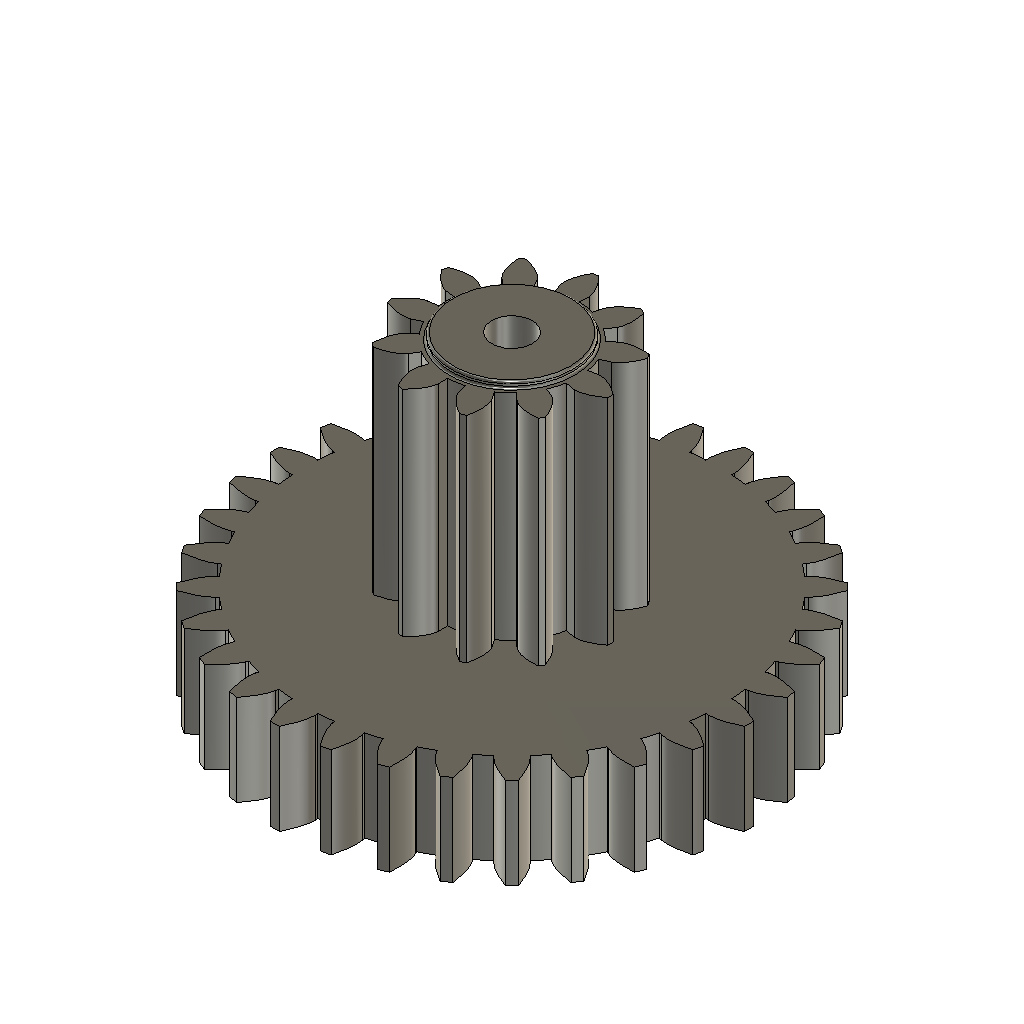
6R2907511A_32T-11T_Gear (Autodesk Fusion 360 design; units mm, degrees)
description: Spur Gear; Module: 0.69; Num Teeth: 32; Pressure Angle: 20.0; Backlash: 0.10 mm
part number: 2026-10-02-15-58-56-443
Autodesk Fusion 360 part; units mm, degrees
(part 1 of 7)
sketch "Base Circle" plane through (0, 0, 0) normal (0, 0, 1) x (1, 0, 0)
  circle A0 centre (0, 0) radius 10.24167
  circle A1 centre (0, 0) radius 1
extrude "Extrude1" add sketch "Base Circle" along normal blind 4.5 contours A0 picked at (7.122983, -0.508814) makes body 1
sketch "Gear Tooth" plane through (0, 0, 0) normal (0, 0, 1) x (1, 0, 0)
  spline S0 degree 5 poles (10.354449, -0.639965) (10.358374, -0.640208) (10.366227, -0.640603) (10.378011, -0.640924) (10.393732, -0.640838) (10.413398, -0.640021) (10.433079, -0.63869) (10.452771, -0.637035) (10.472474, -0.635204) (10.492186, -0.633256) (10.511906, -0.631191) (10.531631, -0.628972) (10.55136, -0.626547) (10.571092, -0.62388) (10.590826, -0.620964) (10.610561, -0.617818) (10.630298, -0.614469) (10.650036, -0.610951) (10.669774, -0.607289) (10.689512, -0.603492) (10.709251, -0.59956) (10.728988, -0.595488) (10.748725, -0.591267) (10.768459, -0.586892) (10.788192, -0.582365) (10.807922, -0.577689) (10.827649, -0.572872) (10.847374, -0.567922) (10.867095, -0.562843) (10.886813, -0.557639) (10.906526, -0.552312) (10.926236, -0.546861) (10.945941, -0.541285) (10.965642, -0.535586) (10.985337, -0.529764) (11.005027, -0.523821) (11.024712, -0.517759) (11.044391, -0.511582) (11.064064, -0.50529) (11.08373, -0.498885) (11.10339, -0.492368) (11.123044, -0.485741) (11.14269, -0.479003) (11.162329, -0.472156) (11.181961, -0.465201) (11.201585, -0.458138) (11.221201, -0.450968) (11.240809, -0.443694) (11.260409, -0.436315) (11.28, -0.428833) (11.299582, -0.421248) (11.319155, -0.413562) (11.33872, -0.405774) (11.358274, -0.397886) (11.377819, -0.389899) (11.397354, -0.381812) (11.41688, -0.373627) (11.436394, -0.365345) (11.455899, -0.356966) (11.475393, -0.34849) (11.494875, -0.339919) (11.514347, -0.331253) (11.533808, -0.322492) (11.553257, -0.313638) (11.572695, -0.304689) (11.592121, -0.295649) (11.611534, -0.286515) (11.630936, -0.277291) (11.650324, -0.267975) (11.6697, -0.258568) (11.689064, -0.249071) (11.704544, -0.241401) (11.716149, -0.235607) (11.723883, -0.231727) (11.727749, -0.229783) knots 0 0 0 0 0 0 0.01428571 0.02857143 0.04285714 0.05714286 0.07142857 0.08571429 0.1 0.11428571 0.12857143 0.14285714 0.15714286 0.17142857 0.18571429 0.2 0.21428571 0.22857143 0.24285714 0.25714286 0.27142857 0.28571429 0.3 0.31428571 0.32857143 0.34285714 0.35714286 0.37142857 0.38571429 0.4 0.41428571 0.42857143 0.44285714 0.45714286 0.47142857 0.48571429 0.5 0.51428571 0.52857143 0.54285714 0.55714286 0.57142857 0.58571429 0.6 0.61428571 0.62857143 0.64285714 0.65714286 0.67142857 0.68571429 0.7 0.71428571 0.72857143 0.74285714 0.75714286 0.77142857 0.78571429 0.8 0.81428571 0.82857143 0.84285714 0.85714286 0.87142857 0.88571429 0.9 0.91428571 0.92857143 0.94285714 0.95714286 0.97142857 0.98571429 1 1 1 1 1 1
  spline S1 degree 5 poles (10.354449, 0.639965) (10.358374, 0.640208) (10.366227, 0.640603) (10.378011, 0.640924) (10.393732, 0.640838) (10.413398, 0.640021) (10.433079, 0.63869) (10.452771, 0.637035) (10.472474, 0.635204) (10.492186, 0.633256) (10.511906, 0.631191) (10.531631, 0.628972) (10.55136, 0.626547) (10.571092, 0.62388) (10.590826, 0.620964) (10.610561, 0.617818) (10.630298, 0.614469) (10.650036, 0.610951) (10.669774, 0.607289) (10.689512, 0.603492) (10.709251, 0.59956) (10.728988, 0.595488) (10.748725, 0.591267) (10.768459, 0.586892) (10.788192, 0.582365) (10.807922, 0.577689) (10.827649, 0.572872) (10.847374, 0.567922) (10.867095, 0.562843) (10.886813, 0.557639) (10.906526, 0.552312) (10.926236, 0.546861) (10.945941, 0.541285) (10.965642, 0.535586) (10.985337, 0.529764) (11.005027, 0.523821) (11.024712, 0.517759) (11.044391, 0.511582) (11.064064, 0.50529) (11.08373, 0.498885) (11.10339, 0.492368) (11.123044, 0.485741) (11.14269, 0.479003) (11.162329, 0.472156) (11.181961, 0.465201) (11.201585, 0.458138) (11.221201, 0.450968) (11.240809, 0.443694) (11.260409, 0.436315) (11.28, 0.428833) (11.299582, 0.421248) (11.319155, 0.413562) (11.33872, 0.405774) (11.358274, 0.397886) (11.377819, 0.389899) (11.397354, 0.381812) (11.41688, 0.373627) (11.436394, 0.365345) (11.455899, 0.356966) (11.475393, 0.34849) (11.494875, 0.339919) (11.514347, 0.331253) (11.533808, 0.322492) (11.553257, 0.313638) (11.572695, 0.304689) (11.592121, 0.295649) (11.611534, 0.286515) (11.630936, 0.277291) (11.650324, 0.267975) (11.6697, 0.258568) (11.689064, 0.249071) (11.704544, 0.241401) (11.716149, 0.235607) (11.723883, 0.231727) (11.727749, 0.229783) knots 0 0 0 0 0 0 0.01428571 0.02857143 0.04285714 0.05714286 0.07142857 0.08571429 0.1 0.11428571 0.12857143 0.14285714 0.15714286 0.17142857 0.18571429 0.2 0.21428571 0.22857143 0.24285714 0.25714286 0.27142857 0.28571429 0.3 0.31428571 0.32857143 0.34285714 0.35714286 0.37142857 0.38571429 0.4 0.41428571 0.42857143 0.44285714 0.45714286 0.47142857 0.48571429 0.5 0.51428571 0.52857143 0.54285714 0.55714286 0.57142857 0.58571429 0.6 0.61428571 0.62857143 0.64285714 0.65714286 0.67142857 0.68571429 0.7 0.71428571 0.72857143 0.74285714 0.75714286 0.77142857 0.78571429 0.8 0.81428571 0.82857143 0.84285714 0.85714286 0.87142857 0.88571429 0.9 0.91428571 0.92857143 0.94285714 0.95714286 0.97142857 0.98571429 1 1 1 1 1 1
  arc A0 (11.727749, -0.229783) -> (11.727749, 0.229783) centre (0, 0) ccw
  line L0 (10.212184, -0.631172) -> (10.354449, -0.639965)
  line L1 (10.212184, 0.631172) -> (10.354449, 0.639965)
  line L2 (10.212184, -0.631172) -> (10.212184, 0.631172)
  point P0 (10.45165, -0.637089)
  point P1 (10.549289, -0.626753)
  point P2 (10.647192, -0.61143)
  point P3 (10.745282, -0.591976)
  point P4 (10.843507, -0.56887)
  point P5 (10.941824, -0.542429)
  point P6 (11.040197, -0.512879)
  point P7 (11.138591, -0.48039)
  point P8 (11.236976, -0.445097)
  point P9 (11.335322, -0.407108)
  point P10 (11.4336, -0.366512)
  point P11 (11.531782, -0.323384)
  point P12 (11.62984, -0.27779)
  point P13 (10.45165, 0.637089)
  point P14 (10.549289, 0.626753)
  point P15 (10.647192, 0.61143)
  point P16 (10.745282, 0.591976)
  point P17 (10.843507, 0.56887)
  point P18 (10.941824, 0.542429)
  point P19 (11.040197, 0.512879)
  point P20 (11.138591, 0.48039)
  point P21 (11.236976, 0.445097)
  point P22 (11.335322, 0.407108)
  point P23 (11.4336, 0.366512)
  point P24 (11.531782, 0.323384)
  point P25 (11.62984, 0.27779)
extrude "Extrude2" add sketch "Gear Tooth" along normal blind 4.5 contours S0 S1 A0 L0 L1 L2 picked at (11.141488, 0.130034) bodies 1
fillet "Fillet1" radius 0.4 2 edges at (10.222164, -0.631789, 2.25) (10.222164, 0.631789, 2.25) on bodies 1
pattern_circular "C-Pattern1" count 32 over 360 about axis through (0, 0, 0) along (0, 0, 1) of "Extrude2", "Fillet1"
sketch "Diametrial Pitch Circle" plane through (0, 0, 0) normal (0, 0, 1) x (1, 0, 0)
  circle A0 centre (0, 0) radius 11.04 construction
sketch "Base Circle (1)" plane through (0, 0, 0) normal (0, 0, 1) x (1, 0, 0)
  circle A0 centre (0, 0) radius 10.24167
  circle A1 centre (0, 0) radius 1
extrude "Extrude3" add sketch "Base Circle (1)" along normal blind 4.5 separate body contours A0 picked at (7.122983, -0.508814) makes body 2
sketch "Gear Tooth (1)" plane through (0, 0, 0) normal (0, 0, 1) x (1, 0, 0)
  spline S0 degree 5 poles (10.354449, -0.639965) (10.358374, -0.640208) (10.366227, -0.640603) (10.378011, -0.640924) (10.393732, -0.640838) (10.413398, -0.640021) (10.433079, -0.63869) (10.452771, -0.637035) (10.472474, -0.635204) (10.492186, -0.633256) (10.511906, -0.631191) (10.531631, -0.628972) (10.55136, -0.626547) (10.571092, -0.62388) (10.590826, -0.620964) (10.610561, -0.617818) (10.630298, -0.614469) (10.650036, -0.610951) (10.669774, -0.607289) (10.689512, -0.603492) (10.709251, -0.59956) (10.728988, -0.595488) (10.748725, -0.591267) (10.768459, -0.586892) (10.788192, -0.582365) (10.807922, -0.577689) (10.827649, -0.572872) (10.847374, -0.567922) (10.867095, -0.562843) (10.886813, -0.557639) (10.906526, -0.552312) (10.926236, -0.546861) (10.945941, -0.541285) (10.965642, -0.535586) (10.985337, -0.529764) (11.005027, -0.523821) (11.024712, -0.517759) (11.044391, -0.511582) (11.064064, -0.50529) (11.08373, -0.498885) (11.10339, -0.492368) (11.123044, -0.485741) (11.14269, -0.479003) (11.162329, -0.472156) (11.181961, -0.465201) (11.201585, -0.458138) (11.221201, -0.450968) (11.240809, -0.443694) (11.260409, -0.436315) (11.28, -0.428833) (11.299582, -0.421248) (11.319155, -0.413562) (11.33872, -0.405774) (11.358274, -0.397886) (11.377819, -0.389899) (11.397354, -0.381812) (11.41688, -0.373627) (11.436394, -0.365345) (11.455899, -0.356966) (11.475393, -0.34849) (11.494875, -0.339919) (11.514347, -0.331253) (11.533808, -0.322492) (11.553257, -0.313638) (11.572695, -0.304689) (11.592121, -0.295649) (11.611534, -0.286515) (11.630936, -0.277291) (11.650324, -0.267975) (11.6697, -0.258568) (11.689064, -0.249071) (11.704544, -0.241401) (11.716149, -0.235607) (11.723883, -0.231727) (11.727749, -0.229783) knots 0 0 0 0 0 0 0.01428571 0.02857143 0.04285714 0.05714286 0.07142857 0.08571429 0.1 0.11428571 0.12857143 0.14285714 0.15714286 0.17142857 0.18571429 0.2 0.21428571 0.22857143 0.24285714 0.25714286 0.27142857 0.28571429 0.3 0.31428571 0.32857143 0.34285714 0.35714286 0.37142857 0.38571429 0.4 0.41428571 0.42857143 0.44285714 0.45714286 0.47142857 0.48571429 0.5 0.51428571 0.52857143 0.54285714 0.55714286 0.57142857 0.58571429 0.6 0.61428571 0.62857143 0.64285714 0.65714286 0.67142857 0.68571429 0.7 0.71428571 0.72857143 0.74285714 0.75714286 0.77142857 0.78571429 0.8 0.81428571 0.82857143 0.84285714 0.85714286 0.87142857 0.88571429 0.9 0.91428571 0.92857143 0.94285714 0.95714286 0.97142857 0.98571429 1 1 1 1 1 1
  spline S1 degree 5 poles (10.354449, 0.639965) (10.358374, 0.640208) (10.366227, 0.640603) (10.378011, 0.640924) (10.393732, 0.640838) (10.413398, 0.640021) (10.433079, 0.63869) (10.452771, 0.637035) (10.472474, 0.635204) (10.492186, 0.633256) (10.511906, 0.631191) (10.531631, 0.628972) (10.55136, 0.626547) (10.571092, 0.62388) (10.590826, 0.620964) (10.610561, 0.617818) (10.630298, 0.614469) (10.650036, 0.610951) (10.669774, 0.607289) (10.689512, 0.603492) (10.709251, 0.59956) (10.728988, 0.595488) (10.748725, 0.591267) (10.768459, 0.586892) (10.788192, 0.582365) (10.807922, 0.577689) (10.827649, 0.572872) (10.847374, 0.567922) (10.867095, 0.562843) (10.886813, 0.557639) (10.906526, 0.552312) (10.926236, 0.546861) (10.945941, 0.541285) (10.965642, 0.535586) (10.985337, 0.529764) (11.005027, 0.523821) (11.024712, 0.517759) (11.044391, 0.511582) (11.064064, 0.50529) (11.08373, 0.498885) (11.10339, 0.492368) (11.123044, 0.485741) (11.14269, 0.479003) (11.162329, 0.472156) (11.181961, 0.465201) (11.201585, 0.458138) (11.221201, 0.450968) (11.240809, 0.443694) (11.260409, 0.436315) (11.28, 0.428833) (11.299582, 0.421248) (11.319155, 0.413562) (11.33872, 0.405774) (11.358274, 0.397886) (11.377819, 0.389899) (11.397354, 0.381812) (11.41688, 0.373627) (11.436394, 0.365345) (11.455899, 0.356966) (11.475393, 0.34849) (11.494875, 0.339919) (11.514347, 0.331253) (11.533808, 0.322492) (11.553257, 0.313638) (11.572695, 0.304689) (11.592121, 0.295649) (11.611534, 0.286515) (11.630936, 0.277291) (11.650324, 0.267975) (11.6697, 0.258568) (11.689064, 0.249071) (11.704544, 0.241401) (11.716149, 0.235607) (11.723883, 0.231727) (11.727749, 0.229783) knots 0 0 0 0 0 0 0.01428571 0.02857143 0.04285714 0.05714286 0.07142857 0.08571429 0.1 0.11428571 0.12857143 0.14285714 0.15714286 0.17142857 0.18571429 0.2 0.21428571 0.22857143 0.24285714 0.25714286 0.27142857 0.28571429 0.3 0.31428571 0.32857143 0.34285714 0.35714286 0.37142857 0.38571429 0.4 0.41428571 0.42857143 0.44285714 0.45714286 0.47142857 0.48571429 0.5 0.51428571 0.52857143 0.54285714 0.55714286 0.57142857 0.58571429 0.6 0.61428571 0.62857143 0.64285714 0.65714286 0.67142857 0.68571429 0.7 0.71428571 0.72857143 0.74285714 0.75714286 0.77142857 0.78571429 0.8 0.81428571 0.82857143 0.84285714 0.85714286 0.87142857 0.88571429 0.9 0.91428571 0.92857143 0.94285714 0.95714286 0.97142857 0.98571429 1 1 1 1 1 1
  arc A0 (11.727749, -0.229783) -> (11.727749, 0.229783) centre (0, 0) ccw
  line L0 (10.212184, -0.631172) -> (10.354449, -0.639965)
  line L1 (10.212184, 0.631172) -> (10.354449, 0.639965)
  line L2 (10.212184, -0.631172) -> (10.212184, 0.631172)
  point P0 (10.45165, -0.637089)
  point P1 (10.549289, -0.626753)
  point P2 (10.647192, -0.61143)
  point P3 (10.745282, -0.591976)
  point P4 (10.843507, -0.56887)
  point P5 (10.941824, -0.542429)
  point P6 (11.040197, -0.512879)
  point P7 (11.138591, -0.48039)
  point P8 (11.236976, -0.445097)
  point P9 (11.335322, -0.407108)
  point P10 (11.4336, -0.366512)
  point P11 (11.531782, -0.323384)
  point P12 (11.62984, -0.27779)
  point P13 (10.45165, 0.637089)
  point P14 (10.549289, 0.626753)
  point P15 (10.647192, 0.61143)
  point P16 (10.745282, 0.591976)
  point P17 (10.843507, 0.56887)
  point P18 (10.941824, 0.542429)
  point P19 (11.040197, 0.512879)
  point P20 (11.138591, 0.48039)
  point P21 (11.236976, 0.445097)
  point P22 (11.335322, 0.407108)
  point P23 (11.4336, 0.366512)
  point P24 (11.531782, 0.323384)
  point P25 (11.62984, 0.27779)
extrude "Extrude4" add sketch "Gear Tooth (1)" along normal blind 4.5 contours S0 S1 A0 L0 L1 L2 picked at (11.141488, 0.130034) bodies 2
pattern_circular "C-Pattern2" count 32 over 360 about axis through (0, 0, 0) along (0, 0, 1) of "Extrude4"
sketch "Diametrial Pitch Circle (1)" plane through (0, 0, 0) normal (0, 0, 1) x (1, 0, 0)
  circle A0 centre (0, 0) radius 11.04 construction
sketch "Sketch7" plane through (0, 0, 0) normal (0, 0, -1) x (1, 0, 0)
  arc A0 (9.902493, 2.613895) -> (9.685824, 3.328156) centre (0, 0) ccw
  line L0 (9.685824, 3.328156) -> (9.811167, 3.371225)
  spline S0 degree 5 poles (9.811167, 3.371225) (9.814887, 3.372504) (9.822293, 3.375144) (9.833303, 3.379356) (9.847794, 3.385452) (9.865651, 3.393733) (9.883324, 3.402494) (9.900884, 3.411559) (9.918387, 3.42079) (9.935853, 3.430133) (9.953281, 3.439587) (9.970655, 3.449186) (9.987955, 3.458976) (10.005164, 3.468992) (10.02228, 3.479237) (10.039309, 3.489697) (10.056262, 3.500343) (10.073151, 3.511147) (10.089985, 3.522084) (10.106768, 3.533146) (10.123499, 3.544331) (10.140176, 3.555647) (10.156795, 3.567099) (10.173353, 3.578693) (10.189851, 3.590427) (10.20629, 3.602297) (10.222672, 3.614297) (10.239001, 3.626419) (10.255277, 3.638658) (10.271503, 3.651011) (10.287677, 3.663477) (10.3038, 3.676056) (10.319872, 3.688748) (10.335892, 3.701553) (10.35186, 3.714469) (10.367777, 3.727494) (10.383644, 3.740627) (10.39946, 3.753866) (10.415228, 3.767207) (10.430947, 3.78065) (10.446616, 3.794194) (10.462238, 3.807838) (10.47781, 3.821582) (10.493334, 3.835423) (10.508809, 3.849362) (10.524237, 3.863397) (10.539616, 3.877528) (10.554948, 3.891752) (10.570232, 3.90607) (10.585468, 3.920479) (10.600657, 3.93498) (10.615799, 3.949572) (10.630894, 3.964254) (10.645942, 3.979024) (10.660942, 3.993884) (10.675896, 4.00883) (10.690802, 4.023864) (10.705662, 4.038984) (10.720475, 4.054189) (10.735242, 4.069479) (10.749962, 4.084854) (10.764635, 4.100312) (10.779262, 4.115853) (10.793842, 4.131477) (10.808376, 4.147182) (10.822863, 4.162969) (10.837304, 4.178836) (10.851698, 4.194783) (10.866046, 4.21081) (10.880347, 4.226915) (10.894602, 4.2431) (10.905969, 4.25611) (10.914473, 4.265903) (10.920134, 4.272447) (10.922961, 4.275724) knots 0 0 0 0 0 0 0.01428571 0.02857143 0.04285714 0.05714286 0.07142857 0.08571429 0.1 0.11428571 0.12857143 0.14285714 0.15714286 0.17142857 0.18571429 0.2 0.21428571 0.22857143 0.24285714 0.25714286 0.27142857 0.28571429 0.3 0.31428571 0.32857143 0.34285714 0.35714286 0.37142857 0.38571429 0.4 0.41428571 0.42857143 0.44285714 0.45714286 0.47142857 0.48571429 0.5 0.51428571 0.52857143 0.54285714 0.55714286 0.57142857 0.58571429 0.6 0.61428571 0.62857143 0.64285714 0.65714286 0.67142857 0.68571429 0.7 0.71428571 0.72857143 0.74285714 0.75714286 0.77142857 0.78571429 0.8 0.81428571 0.82857143 0.84285714 0.85714286 0.87142857 0.88571429 0.9 0.91428571 0.92857143 0.94285714 0.95714286 0.97142857 0.98571429 1 1 1 1 1 1
  arc A1 (10.922961, 4.275724) -> (10.747093, 4.700307) centre (0, 0) ccw
  spline S1 degree 5 poles (9.321359, 4.553726) (9.324893, 4.555453) (9.331997, 4.558823) (9.342761, 4.56363) (9.357318, 4.569566) (9.3758, 4.576337) (9.394492, 4.582638) (9.413318, 4.588646) (9.432222, 4.594494) (9.451179, 4.600239) (9.470188, 4.605877) (9.489261, 4.611375) (9.508416, 4.616685) (9.527667, 4.621772) (9.547014, 4.62663) (9.566452, 4.631275) (9.585968, 4.635734) (9.605549, 4.640037) (9.625186, 4.644207) (9.644875, 4.648253) (9.664616, 4.652174) (9.684409, 4.655965) (9.704259, 4.659618) (9.724165, 4.663129) (9.744128, 4.666497) (9.764146, 4.669728) (9.784215, 4.672827) (9.804332, 4.675801) (9.824496, 4.678656) (9.844704, 4.681394) (9.864956, 4.684017) (9.885251, 4.686523) (9.90559, 4.688913) (9.925972, 4.691186) (9.946396, 4.693344) (9.966862, 4.695389) (9.987368, 4.697322) (10.007913, 4.699145) (10.028496, 4.700861) (10.049117, 4.70247) (10.069774, 4.703973) (10.090467, 4.705371) (10.111197, 4.706664) (10.131961, 4.707854) (10.15276, 4.70894) (10.173594, 4.709925) (10.19446, 4.710808) (10.215359, 4.711591) (10.236291, 4.712274) (10.257254, 4.712859) (10.278248, 4.713345) (10.299273, 4.713734) (10.320328, 4.714027) (10.341413, 4.714222) (10.362527, 4.714322) (10.383669, 4.714327) (10.40484, 4.714237) (10.426039, 4.714053) (10.447266, 4.713776) (10.468519, 4.713406) (10.489799, 4.712943) (10.511105, 4.712388) (10.532437, 4.711741) (10.553794, 4.711004) (10.575176, 4.710175) (10.596583, 4.709256) (10.618014, 4.708248) (10.639469, 4.707149) (10.660947, 4.705962) (10.682448, 4.704686) (10.703971, 4.703322) (10.721209, 4.70216) (10.734147, 4.701249) (10.742777, 4.700624) (10.747093, 4.700307) knots 0 0 0 0 0 0 0.01428571 0.02857143 0.04285714 0.05714286 0.07142857 0.08571429 0.1 0.11428571 0.12857143 0.14285714 0.15714286 0.17142857 0.18571429 0.2 0.21428571 0.22857143 0.24285714 0.25714286 0.27142857 0.28571429 0.3 0.31428571 0.32857143 0.34285714 0.35714286 0.37142857 0.38571429 0.4 0.41428571 0.42857143 0.44285714 0.45714286 0.47142857 0.48571429 0.5 0.51428571 0.52857143 0.54285714 0.55714286 0.57142857 0.58571429 0.6 0.61428571 0.62857143 0.64285714 0.65714286 0.67142857 0.68571429 0.7 0.71428571 0.72857143 0.74285714 0.75714286 0.77142857 0.78571429 0.8 0.81428571 0.82857143 0.84285714 0.85714286 0.87142857 0.88571429 0.9 0.91428571 0.92857143 0.94285714 0.95714286 0.97142857 0.98571429 1 1 1 1 1 1
  line L1 (9.321359, 4.553726) -> (9.202273, 4.49555)
  arc A2 (9.202273, 4.49555) -> (8.850422, 5.153817) centre (0, 0) ccw
  line L2 (8.850422, 5.153817) -> (8.964955, 5.220512)
  spline S2 degree 5 poles (8.964955, 5.220512) (8.968354, 5.222491) (8.975102, 5.226526) (8.985079, 5.232805) (8.998103, 5.241611) (9.014001, 5.253216) (9.029625, 5.265257) (9.045079, 5.277573) (9.060444, 5.290042) (9.075752, 5.302613) (9.091001, 5.315285) (9.106169, 5.32809) (9.121226, 5.341066) (9.136151, 5.354247) (9.150939, 5.367634) (9.1656, 5.381215) (9.180151, 5.394965) (9.194607, 5.408855) (9.208984, 5.422867) (9.223287, 5.43699) (9.237514, 5.451225) (9.251663, 5.465576) (9.265728, 5.480051) (9.279706, 5.494652) (9.293598, 5.50938) (9.307405, 5.524229) (9.321132, 5.539194) (9.334782, 5.554268) (9.348358, 5.569447) (9.361862, 5.584729) (9.375293, 5.600111) (9.388653, 5.615593) (9.401939, 5.631177) (9.415153, 5.646861) (9.428295, 5.662644) (9.441365, 5.678525) (9.454365, 5.694501) (9.467295, 5.71057) (9.480157, 5.726731) (9.492951, 5.742983) (9.505677, 5.759324) (9.518336, 5.775753) (9.530928, 5.79227) (9.543454, 5.808874) (9.555912, 5.825565) (9.568305, 5.84234) (9.580632, 5.859199) (9.592894, 5.876141) (9.605091, 5.893165) (9.617224, 5.910271) (9.629292, 5.927456) (9.641296, 5.944722) (9.653237, 5.962066) (9.665114, 5.979489) (9.676927, 5.996989) (9.688677, 6.014566) (9.700365, 6.032219) (9.711989, 6.049947) (9.723551, 6.06775) (9.735051, 6.085627) (9.746489, 6.103578) (9.757864, 6.121602) (9.769178, 6.139698) (9.78043, 6.157866) (9.791621, 6.176105) (9.80275, 6.194414) (9.813817, 6.212794) (9.824824, 6.231243) (9.835769, 6.249761) (9.846654, 6.268347) (9.857477, 6.287001) (9.866088, 6.301979) (9.872518, 6.313243) (9.876793, 6.320766) (9.878928, 6.324531) knots 0 0 0 0 0 0 0.01428571 0.02857143 0.04285714 0.05714286 0.07142857 0.08571429 0.1 0.11428571 0.12857143 0.14285714 0.15714286 0.17142857 0.18571429 0.2 0.21428571 0.22857143 0.24285714 0.25714286 0.27142857 0.28571429 0.3 0.31428571 0.32857143 0.34285714 0.35714286 0.37142857 0.38571429 0.4 0.41428571 0.42857143 0.44285714 0.45714286 0.47142857 0.48571429 0.5 0.51428571 0.52857143 0.54285714 0.55714286 0.57142857 0.58571429 0.6 0.61428571 0.62857143 0.64285714 0.65714286 0.67142857 0.68571429 0.7 0.71428571 0.72857143 0.74285714 0.75714286 0.77142857 0.78571429 0.8 0.81428571 0.82857143 0.84285714 0.85714286 0.87142857 0.88571429 0.9 0.91428571 0.92857143 0.94285714 0.95714286 0.97142857 0.98571429 1 1 1 1 1 1
  arc A3 (9.878928, 6.324531) -> (9.623607, 6.706646) centre (0, 0) ccw
  spline S3 degree 5 poles (8.253864, 6.284735) (8.256993, 6.287118) (8.263303, 6.291809) (8.272922, 6.298623) (8.286042, 6.307285) (8.302848, 6.317532) (8.319951, 6.327359) (8.337244, 6.336924) (8.354643, 6.346348) (8.372116, 6.35568) (8.389659, 6.364918) (8.407293, 6.374032) (8.425044, 6.382977) (8.442932, 6.391721) (8.46096, 6.400261) (8.479118, 6.408609) (8.497389, 6.41679) (8.515755, 6.42483) (8.534201, 6.432751) (8.552723, 6.44056) (8.571319, 6.448257) (8.589992, 6.455837) (8.608748, 6.463292) (8.627587, 6.470618) (8.646509, 6.477817) (8.665512, 6.484891) (8.684591, 6.491846) (8.703741, 6.498688) (8.72296, 6.505421) (8.742246, 6.512049) (8.761597, 6.518572) (8.781014, 6.524989) (8.800496, 6.531301) (8.820042, 6.537507) (8.839653, 6.543609) (8.859327, 6.549607) (8.879061, 6.555503) (8.898856, 6.561299) (8.918709, 6.566998) (8.938619, 6.572598) (8.958586, 6.578103) (8.97861, 6.583511) (8.998688, 6.588824) (9.018822, 6.594041) (9.039009, 6.599165) (9.05925, 6.604195) (9.079543, 6.609132) (9.099888, 6.613977) (9.120284, 6.61873) (9.14073, 6.623394) (9.161226, 6.627966) (9.181771, 6.63245) (9.202365, 6.636844) (9.223006, 6.641149) (9.243695, 6.645367) (9.26443, 6.649496) (9.285212, 6.653538) (9.30604, 6.657494) (9.326912, 6.661363) (9.347829, 6.665146) (9.368791, 6.668843) (9.389796, 6.672456) (9.410844, 6.675983) (9.431935, 6.679426) (9.453068, 6.682785) (9.474243, 6.68606) (9.495458, 6.689252) (9.516715, 6.69236) (9.538012, 6.695386) (9.559349, 6.698329) (9.580725, 6.70119) (9.597858, 6.703414) (9.610725, 6.705044) (9.619311, 6.706115) (9.623607, 6.706646) knots 0 0 0 0 0 0 0.01428571 0.02857143 0.04285714 0.05714286 0.07142857 0.08571429 0.1 0.11428571 0.12857143 0.14285714 0.15714286 0.17142857 0.18571429 0.2 0.21428571 0.22857143 0.24285714 0.25714286 0.27142857 0.28571429 0.3 0.31428571 0.32857143 0.34285714 0.35714286 0.37142857 0.38571429 0.4 0.41428571 0.42857143 0.44285714 0.45714286 0.47142857 0.48571429 0.5 0.51428571 0.52857143 0.54285714 0.55714286 0.57142857 0.58571429 0.6 0.61428571 0.62857143 0.64285714 0.65714286 0.67142857 0.68571429 0.7 0.71428571 0.72857143 0.74285714 0.75714286 0.77142857 0.78571429 0.8 0.81428571 0.82857143 0.84285714 0.85714286 0.87142857 0.88571429 0.9 0.91428571 0.92857143 0.94285714 0.95714286 0.97142857 0.98571429 1 1 1 1 1 1
  line L3 (8.253864, 6.284735) -> (8.148416, 6.204444)
  arc A4 (8.148416, 6.204444) -> (7.674904, 6.78142) centre (0, 0) ccw
  line L4 (7.674904, 6.78142) -> (7.774224, 6.869177)
  spline S4 degree 5 poles (7.774224, 6.869177) (7.777172, 6.871782) (7.783004, 6.877055) (7.791564, 6.88516) (7.802619, 6.896338) (7.815948, 6.910821) (7.828922, 6.925679) (7.841677, 6.940773) (7.854315, 6.956) (7.866876, 6.971316) (7.87936, 6.98672) (7.891738, 7.002237) (7.903974, 7.017902) (7.91604, 7.033741) (7.927933, 7.049757) (7.939663, 7.065937) (7.951251, 7.08226) (7.96272, 7.098705) (7.974087, 7.115252) (7.98536, 7.131894) (7.996537, 7.148631) (8.007614, 7.165467) (8.018585, 7.182407) (8.029446, 7.199455) (8.040198, 7.216609) (8.050843, 7.233867) (8.061386, 7.251222) (8.071833, 7.26867) (8.082187, 7.286206) (8.09245, 7.303828) (8.102622, 7.321535) (8.112704, 7.339327) (8.122696, 7.357203) (8.132596, 7.375163) (8.142406, 7.393207) (8.152127, 7.411332) (8.16176, 7.429537) (8.171306, 7.447821) (8.180768, 7.466181) (8.190146, 7.484616) (8.19944, 7.503126) (8.20865, 7.521709) (8.217778, 7.540365) (8.226824, 7.559094) (8.235787, 7.577894) (8.244669, 7.596765) (8.25347, 7.615705) (8.262191, 7.634714) (8.270833, 7.65379) (8.279395, 7.672934) (8.287879, 7.692144) (8.296284, 7.711419) (8.304611, 7.73076) (8.312861, 7.750165) (8.321033, 7.769633) (8.329129, 7.789165) (8.337147, 7.808759) (8.34509, 7.828414) (8.352957, 7.848131) (8.360748, 7.867908) (8.368464, 7.887745) (8.376104, 7.907642) (8.38367, 7.927597) (8.391162, 7.947611) (8.398579, 7.967683) (8.405922, 7.987812) (8.413192, 8.007998) (8.420387, 8.028239) (8.42751, 8.048537) (8.434559, 8.068889) (8.441536, 8.089297) (8.447059, 8.105667) (8.451168, 8.117969) (8.453893, 8.126181) (8.455252, 8.13029) knots 0 0 0 0 0 0 0.01428571 0.02857143 0.04285714 0.05714286 0.07142857 0.08571429 0.1 0.11428571 0.12857143 0.14285714 0.15714286 0.17142857 0.18571429 0.2 0.21428571 0.22857143 0.24285714 0.25714286 0.27142857 0.28571429 0.3 0.31428571 0.32857143 0.34285714 0.35714286 0.37142857 0.38571429 0.4 0.41428571 0.42857143 0.44285714 0.45714286 0.47142857 0.48571429 0.5 0.51428571 0.52857143 0.54285714 0.55714286 0.57142857 0.58571429 0.6 0.61428571 0.62857143 0.64285714 0.65714286 0.67142857 0.68571429 0.7 0.71428571 0.72857143 0.74285714 0.75714286 0.77142857 0.78571429 0.8 0.81428571 0.82857143 0.84285714 0.85714286 0.87142857 0.88571429 0.9 0.91428571 0.92857143 0.94285714 0.95714286 0.97142857 0.98571429 1 1 1 1 1 1
  arc A5 (8.455252, 8.13029) -> (8.13029, 8.455252) centre (0, 0) ccw
  spline S5 degree 5 poles (6.869177, 7.774224) (6.871782, 7.777172) (6.877055, 7.783004) (6.88516, 7.791564) (6.896338, 7.802619) (6.910821, 7.815948) (6.925679, 7.828922) (6.940773, 7.841677) (6.956, 7.854315) (6.971316, 7.866876) (6.98672, 7.87936) (7.002237, 7.891738) (7.017902, 7.903974) (7.033741, 7.91604) (7.049757, 7.927933) (7.065937, 7.939663) (7.08226, 7.951251) (7.098705, 7.96272) (7.115252, 7.974087) (7.131894, 7.98536) (7.148631, 7.996537) (7.165467, 8.007614) (7.182407, 8.018585) (7.199455, 8.029446) (7.216609, 8.040198) (7.233867, 8.050843) (7.251222, 8.061386) (7.26867, 8.071833) (7.286206, 8.082187) (7.303828, 8.09245) (7.321535, 8.102622) (7.339327, 8.112704) (7.357203, 8.122696) (7.375163, 8.132596) (7.393207, 8.142406) (7.411332, 8.152127) (7.429537, 8.16176) (7.447821, 8.171306) (7.466181, 8.180768) (7.484616, 8.190146) (7.503126, 8.19944) (7.521709, 8.20865) (7.540365, 8.217778) (7.559094, 8.226824) (7.577894, 8.235787) (7.596765, 8.244669) (7.615705, 8.25347) (7.634714, 8.262191) (7.65379, 8.270833) (7.672934, 8.279395) (7.692144, 8.287879) (7.711419, 8.296284) (7.73076, 8.304611) (7.750165, 8.312861) (7.769633, 8.321033) (7.789165, 8.329129) (7.808759, 8.337147) (7.828414, 8.34509) (7.848131, 8.352957) (7.867908, 8.360748) (7.887745, 8.368464) (7.907642, 8.376104) (7.927597, 8.38367) (7.947611, 8.391162) (7.967683, 8.398579) (7.987812, 8.405922) (8.007998, 8.413192) (8.028239, 8.420387) (8.048537, 8.42751) (8.068889, 8.434559) (8.089297, 8.441536) (8.105667, 8.447059) (8.117969, 8.451168) (8.126181, 8.453893) (8.13029, 8.455252) knots 0 0 0 0 0 0 0.01428571 0.02857143 0.04285714 0.05714286 0.07142857 0.08571429 0.1 0.11428571 0.12857143 0.14285714 0.15714286 0.17142857 0.18571429 0.2 0.21428571 0.22857143 0.24285714 0.25714286 0.27142857 0.28571429 0.3 0.31428571 0.32857143 0.34285714 0.35714286 0.37142857 0.38571429 0.4 0.41428571 0.42857143 0.44285714 0.45714286 0.47142857 0.48571429 0.5 0.51428571 0.52857143 0.54285714 0.55714286 0.57142857 0.58571429 0.6 0.61428571 0.62857143 0.64285714 0.65714286 0.67142857 0.68571429 0.7 0.71428571 0.72857143 0.74285714 0.75714286 0.77142857 0.78571429 0.8 0.81428571 0.82857143 0.84285714 0.85714286 0.87142857 0.88571429 0.9 0.91428571 0.92857143 0.94285714 0.95714286 0.97142857 0.98571429 1 1 1 1 1 1
  line L5 (6.869177, 7.774224) -> (6.78142, 7.674904)
  arc A6 (6.78142, 7.674904) -> (6.204444, 8.148416) centre (0, 0) ccw
  line L6 (6.204444, 8.148416) -> (6.284735, 8.253864)
  spline S6 degree 5 poles (6.284735, 8.253864) (6.287118, 8.256993) (6.291809, 8.263303) (6.298623, 8.272922) (6.307285, 8.286042) (6.317532, 8.302848) (6.327359, 8.319951) (6.336924, 8.337244) (6.346348, 8.354643) (6.35568, 8.372116) (6.364918, 8.389659) (6.374032, 8.407293) (6.382977, 8.425044) (6.391721, 8.442932) (6.400261, 8.46096) (6.408609, 8.479118) (6.41679, 8.497389) (6.42483, 8.515755) (6.432751, 8.534201) (6.44056, 8.552723) (6.448257, 8.571319) (6.455837, 8.589992) (6.463292, 8.608748) (6.470618, 8.627587) (6.477817, 8.646509) (6.484891, 8.665512) (6.491846, 8.684591) (6.498688, 8.703741) (6.505421, 8.72296) (6.512049, 8.742246) (6.518572, 8.761597) (6.524989, 8.781014) (6.531301, 8.800496) (6.537507, 8.820042) (6.543609, 8.839653) (6.549607, 8.859327) (6.555503, 8.879061) (6.561299, 8.898856) (6.566998, 8.918709) (6.572598, 8.938619) (6.578103, 8.958586) (6.583511, 8.97861) (6.588824, 8.998688) (6.594041, 9.018822) (6.599165, 9.039009) (6.604195, 9.05925) (6.609132, 9.079543) (6.613977, 9.099888) (6.61873, 9.120284) (6.623394, 9.14073) (6.627966, 9.161226) (6.63245, 9.181771) (6.636844, 9.202365) (6.641149, 9.223006) (6.645367, 9.243695) (6.649496, 9.26443) (6.653538, 9.285212) (6.657494, 9.30604) (6.661363, 9.326912) (6.665146, 9.347829) (6.668843, 9.368791) (6.672456, 9.389796) (6.675983, 9.410844) (6.679426, 9.431935) (6.682785, 9.453068) (6.68606, 9.474243) (6.689252, 9.495458) (6.69236, 9.516715) (6.695386, 9.538012) (6.698329, 9.559349) (6.70119, 9.580725) (6.703414, 9.597858) (6.705044, 9.610725) (6.706115, 9.619311) (6.706646, 9.623607) knots 0 0 0 0 0 0 0.01428571 0.02857143 0.04285714 0.05714286 0.07142857 0.08571429 0.1 0.11428571 0.12857143 0.14285714 0.15714286 0.17142857 0.18571429 0.2 0.21428571 0.22857143 0.24285714 0.25714286 0.27142857 0.28571429 0.3 0.31428571 0.32857143 0.34285714 0.35714286 0.37142857 0.38571429 0.4 0.41428571 0.42857143 0.44285714 0.45714286 0.47142857 0.48571429 0.5 0.51428571 0.52857143 0.54285714 0.55714286 0.57142857 0.58571429 0.6 0.61428571 0.62857143 0.64285714 0.65714286 0.67142857 0.68571429 0.7 0.71428571 0.72857143 0.74285714 0.75714286 0.77142857 0.78571429 0.8 0.81428571 0.82857143 0.84285714 0.85714286 0.87142857 0.88571429 0.9 0.91428571 0.92857143 0.94285714 0.95714286 0.97142857 0.98571429 1 1 1 1 1 1
  arc A7 (6.706646, 9.623607) -> (6.324531, 9.878928) centre (0, 0) ccw
  spline S7 degree 5 poles (5.220512, 8.964955) (5.222491, 8.968354) (5.226526, 8.975102) (5.232805, 8.985079) (5.241611, 8.998103) (5.253216, 9.014001) (5.265257, 9.029625) (5.277573, 9.045079) (5.290042, 9.060444) (5.302613, 9.075752) (5.315285, 9.091001) (5.32809, 9.106169) (5.341066, 9.121226) (5.354247, 9.136151) (5.367634, 9.150939) (5.381215, 9.1656) (5.394965, 9.180151) (5.408855, 9.194607) (5.422867, 9.208984) (5.43699, 9.223287) (5.451225, 9.237514) (5.465576, 9.251663) (5.480051, 9.265728) (5.494652, 9.279706) (5.50938, 9.293598) (5.524229, 9.307405) (5.539194, 9.321132) (5.554268, 9.334782) (5.569447, 9.348358) (5.584729, 9.361862) (5.600111, 9.375293) (5.615593, 9.388653) (5.631177, 9.401939) (5.646861, 9.415153) (5.662644, 9.428295) (5.678525, 9.441365) (5.694501, 9.454365) (5.71057, 9.467295) (5.726731, 9.480157) (5.742983, 9.492951) (5.759324, 9.505677) (5.775753, 9.518336) (5.79227, 9.530928) (5.808874, 9.543454) (5.825565, 9.555912) (5.84234, 9.568305) (5.859199, 9.580632) (5.876141, 9.592894) (5.893165, 9.605091) (5.910271, 9.617224) (5.927456, 9.629292) (5.944722, 9.641296) (5.962066, 9.653237) (5.979489, 9.665114) (5.996989, 9.676927) (6.014566, 9.688677) (6.032219, 9.700365) (6.049947, 9.711989) (6.06775, 9.723551) (6.085627, 9.735051) (6.103578, 9.746489) (6.121602, 9.757864) (6.139698, 9.769178) (6.157866, 9.78043) (6.176105, 9.791621) (6.194414, 9.80275) (6.212794, 9.813817) (6.231243, 9.824824) (6.249761, 9.835769) (6.268347, 9.846654) (6.287001, 9.857477) (6.301979, 9.866088) (6.313243, 9.872518) (6.320766, 9.876793) (6.324531, 9.878928) knots 0 0 0 0 0 0 0.01428571 0.02857143 0.04285714 0.05714286 0.07142857 0.08571429 0.1 0.11428571 0.12857143 0.14285714 0.15714286 0.17142857 0.18571429 0.2 0.21428571 0.22857143 0.24285714 0.25714286 0.27142857 0.28571429 0.3 0.31428571 0.32857143 0.34285714 0.35714286 0.37142857 0.38571429 0.4 0.41428571 0.42857143 0.44285714 0.45714286 0.47142857 0.48571429 0.5 0.51428571 0.52857143 0.54285714 0.55714286 0.57142857 0.58571429 0.6 0.61428571 0.62857143 0.64285714 0.65714286 0.67142857 0.68571429 0.7 0.71428571 0.72857143 0.74285714 0.75714286 0.77142857 0.78571429 0.8 0.81428571 0.82857143 0.84285714 0.85714286 0.87142857 0.88571429 0.9 0.91428571 0.92857143 0.94285714 0.95714286 0.97142857 0.98571429 1 1 1 1 1 1
  line L7 (5.220512, 8.964955) -> (5.153817, 8.850422)
  arc A8 (5.153817, 8.850422) -> (4.49555, 9.202273) centre (0, 0) ccw
  line L8 (4.49555, 9.202273) -> (4.553726, 9.321359)
  spline S8 degree 5 poles (4.553726, 9.321359) (4.555453, 9.324893) (4.558823, 9.331997) (4.56363, 9.342761) (4.569566, 9.357318) (4.576337, 9.3758) (4.582638, 9.394492) (4.588646, 9.413318) (4.594494, 9.432222) (4.600239, 9.451179) (4.605877, 9.470188) (4.611375, 9.489261) (4.616685, 9.508416) (4.621772, 9.527667) (4.62663, 9.547014) (4.631275, 9.566452) (4.635734, 9.585968) (4.640037, 9.605549) (4.644207, 9.625186) (4.648253, 9.644875) (4.652174, 9.664616) (4.655965, 9.684409) (4.659618, 9.704259) (4.663129, 9.724165) (4.666497, 9.744128) (4.669728, 9.764146) (4.672827, 9.784215) (4.675801, 9.804332) (4.678656, 9.824496) (4.681394, 9.844704) (4.684017, 9.864956) (4.686523, 9.885251) (4.688913, 9.90559) (4.691186, 9.925972) (4.693344, 9.946396) (4.695389, 9.966862) (4.697322, 9.987368) (4.699145, 10.007913) (4.700861, 10.028496) (4.70247, 10.049117) (4.703973, 10.069774) (4.705371, 10.090467) (4.706664, 10.111197) (4.707854, 10.131961) (4.70894, 10.15276) (4.709925, 10.173594) (4.710808, 10.19446) (4.711591, 10.215359) (4.712274, 10.236291) (4.712859, 10.257254) (4.713345, 10.278248) (4.713734, 10.299273) (4.714027, 10.320328) (4.714222, 10.341413) (4.714322, 10.362527) (4.714327, 10.383669) (4.714237, 10.40484) (4.714053, 10.426039) (4.713776, 10.447266) (4.713406, 10.468519) (4.712943, 10.489799) (4.712388, 10.511105) (4.711741, 10.532437) (4.711004, 10.553794) (4.710175, 10.575176) (4.709256, 10.596583) (4.708248, 10.618014) (4.707149, 10.639469) (4.705962, 10.660947) (4.704686, 10.682448) (4.703322, 10.703971) (4.70216, 10.721209) (4.701249, 10.734147) (4.700624, 10.742777) (4.700307, 10.747093) knots 0 0 0 0 0 0 0.01428571 0.02857143 0.04285714 0.05714286 0.07142857 0.08571429 0.1 0.11428571 0.12857143 0.14285714 0.15714286 0.17142857 0.18571429 0.2 0.21428571 0.22857143 0.24285714 0.25714286 0.27142857 0.28571429 0.3 0.31428571 0.32857143 0.34285714 0.35714286 0.37142857 0.38571429 0.4 0.41428571 0.42857143 0.44285714 0.45714286 0.47142857 0.48571429 0.5 0.51428571 0.52857143 0.54285714 0.55714286 0.57142857 0.58571429 0.6 0.61428571 0.62857143 0.64285714 0.65714286 0.67142857 0.68571429 0.7 0.71428571 0.72857143 0.74285714 0.75714286 0.77142857 0.78571429 0.8 0.81428571 0.82857143 0.84285714 0.85714286 0.87142857 0.88571429 0.9 0.91428571 0.92857143 0.94285714 0.95714286 0.97142857 0.98571429 1 1 1 1 1 1
  arc A9 (4.700307, 10.747093) -> (4.275724, 10.922961) centre (0, 0) ccw
  spline S9 degree 5 poles (3.371225, 9.811167) (3.372504, 9.814887) (3.375144, 9.822293) (3.379356, 9.833303) (3.385452, 9.847794) (3.393733, 9.865651) (3.402494, 9.883324) (3.411559, 9.900884) (3.42079, 9.918387) (3.430133, 9.935853) (3.439587, 9.953281) (3.449186, 9.970655) (3.458976, 9.987955) (3.468992, 10.005164) (3.479237, 10.02228) (3.489697, 10.039309) (3.500343, 10.056262) (3.511147, 10.073151) (3.522084, 10.089985) (3.533146, 10.106768) (3.544331, 10.123499) (3.555647, 10.140176) (3.567099, 10.156795) (3.578693, 10.173353) (3.590427, 10.189851) (3.602297, 10.20629) (3.614297, 10.222672) (3.626419, 10.239001) (3.638658, 10.255277) (3.651011, 10.271503) (3.663477, 10.287677) (3.676056, 10.3038) (3.688748, 10.319872) (3.701553, 10.335892) (3.714469, 10.35186) (3.727494, 10.367777) (3.740627, 10.383644) (3.753866, 10.39946) (3.767207, 10.415228) (3.78065, 10.430947) (3.794194, 10.446616) (3.807838, 10.462238) (3.821582, 10.47781) (3.835423, 10.493334) (3.849362, 10.508809) (3.863397, 10.524237) (3.877528, 10.539616) (3.891752, 10.554948) (3.90607, 10.570232) (3.920479, 10.585468) (3.93498, 10.600657) (3.949572, 10.615799) (3.964254, 10.630894) (3.979024, 10.645942) (3.993884, 10.660942) (4.00883, 10.675896) (4.023864, 10.690802) (4.038984, 10.705662) (4.054189, 10.720475) (4.069479, 10.735242) (4.084854, 10.749962) (4.100312, 10.764635) (4.115853, 10.779262) (4.131477, 10.793842) (4.147182, 10.808376) (4.162969, 10.822863) (4.178836, 10.837304) (4.194783, 10.851698) (4.21081, 10.866046) (4.226915, 10.880347) (4.2431, 10.894602) (4.25611, 10.905969) (4.265903, 10.914473) (4.272447, 10.920134) (4.275724, 10.922961) knots 0 0 0 0 0 0 0.01428571 0.02857143 0.04285714 0.05714286 0.07142857 0.08571429 0.1 0.11428571 0.12857143 0.14285714 0.15714286 0.17142857 0.18571429 0.2 0.21428571 0.22857143 0.24285714 0.25714286 0.27142857 0.28571429 0.3 0.31428571 0.32857143 0.34285714 0.35714286 0.37142857 0.38571429 0.4 0.41428571 0.42857143 0.44285714 0.45714286 0.47142857 0.48571429 0.5 0.51428571 0.52857143 0.54285714 0.55714286 0.57142857 0.58571429 0.6 0.61428571 0.62857143 0.64285714 0.65714286 0.67142857 0.68571429 0.7 0.71428571 0.72857143 0.74285714 0.75714286 0.77142857 0.78571429 0.8 0.81428571 0.82857143 0.84285714 0.85714286 0.87142857 0.88571429 0.9 0.91428571 0.92857143 0.94285714 0.95714286 0.97142857 0.98571429 1 1 1 1 1 1
  line L9 (3.371225, 9.811167) -> (3.328156, 9.685824)
  arc A10 (3.328156, 9.685824) -> (2.613895, 9.902493) centre (0, 0) ccw
  line L10 (2.613895, 9.902493) -> (2.647721, 10.03064)
  spline S10 degree 5 poles (2.647721, 10.03064) (2.648725, 10.034443) (2.650644, 10.042068) (2.653259, 10.053562) (2.656241, 10.068998) (2.659277, 10.088446) (2.66181, 10.108008) (2.664029, 10.127644) (2.666077, 10.147326) (2.668013, 10.16704) (2.669834, 10.186783) (2.671506, 10.206562) (2.672977, 10.226385) (2.67421, 10.246258) (2.6752, 10.266182) (2.675964, 10.286152) (2.676531, 10.306163) (2.676931, 10.326208) (2.677189, 10.346281) (2.677316, 10.366381) (2.677311, 10.386507) (2.677168, 10.40666) (2.676878, 10.42684) (2.676437, 10.447049) (2.675847, 10.467286) (2.67511, 10.487549) (2.674234, 10.507837) (2.673227, 10.528148) (2.672093, 10.548481) (2.670836, 10.568835) (2.669457, 10.58921) (2.667956, 10.609604) (2.666332, 10.630019) (2.664585, 10.650452) (2.662717, 10.670905) (2.66073, 10.691376) (2.658625, 10.711865) (2.656405, 10.732371) (2.654072, 10.752894) (2.651628, 10.773432) (2.649072, 10.793986) (2.646406, 10.814554) (2.64363, 10.835138) (2.640746, 10.855735) (2.637754, 10.876347) (2.634655, 10.896972) (2.631451, 10.917609) (2.628141, 10.93826) (2.624728, 10.958922) (2.621212, 10.979597) (2.617593, 11.000282) (2.613873, 11.020979) (2.610052, 11.041687) (2.60613, 11.062404) (2.602109, 11.083132) (2.597989, 11.10387) (2.593771, 11.124616) (2.589455, 11.145372) (2.585042, 11.166136) (2.580532, 11.186909) (2.575927, 11.20769) (2.571226, 11.228478) (2.56643, 11.249274) (2.56154, 11.270077) (2.556556, 11.290887) (2.551478, 11.311703) (2.546308, 11.332526) (2.541045, 11.353354) (2.535691, 11.374187) (2.530245, 11.395026) (2.524708, 11.41587) (2.520205, 11.43255) (2.516788, 11.445062) (2.514491, 11.453404) (2.513338, 11.457575) knots 0 0 0 0 0 0 0.01428571 0.02857143 0.04285714 0.05714286 0.07142857 0.08571429 0.1 0.11428571 0.12857143 0.14285714 0.15714286 0.17142857 0.18571429 0.2 0.21428571 0.22857143 0.24285714 0.25714286 0.27142857 0.28571429 0.3 0.31428571 0.32857143 0.34285714 0.35714286 0.37142857 0.38571429 0.4 0.41428571 0.42857143 0.44285714 0.45714286 0.47142857 0.48571429 0.5 0.51428571 0.52857143 0.54285714 0.55714286 0.57142857 0.58571429 0.6 0.61428571 0.62857143 0.64285714 0.65714286 0.67142857 0.68571429 0.7 0.71428571 0.72857143 0.74285714 0.75714286 0.77142857 0.78571429 0.8 0.81428571 0.82857143 0.84285714 0.85714286 0.87142857 0.88571429 0.9 0.91428571 0.92857143 0.94285714 0.95714286 0.97142857 0.98571429 1 1 1 1 1 1
  arc A11 (2.513338, 11.457575) -> (2.062603, 11.547232) centre (0, 0) ccw
  spline S11 degree 5 poles (1.392385, 10.280342) (1.392912, 10.284239) (1.394057, 10.292018) (1.39604, 10.303638) (1.399192, 10.319041) (1.40383, 10.33817) (1.408975, 10.357212) (1.41444, 10.376203) (1.420079, 10.395171) (1.425835, 10.414124) (1.431708, 10.433062) (1.437733, 10.451975) (1.44396, 10.470852) (1.450425, 10.489684) (1.457135, 10.50847) (1.464071, 10.527213) (1.471206, 10.545917) (1.478507, 10.564589) (1.48595, 10.583233) (1.493525, 10.601852) (1.501231, 10.620444) (1.509076, 10.639008) (1.517066, 10.657541) (1.525207, 10.676043) (1.533497, 10.694513) (1.541932, 10.712952) (1.550505, 10.731361) (1.559208, 10.74974) (1.568037, 10.768092) (1.576987, 10.786416) (1.586058, 10.804711) (1.59525, 10.822979) (1.604563, 10.841218) (1.613996, 10.859428) (1.623549, 10.877609) (1.633219, 10.895761) (1.643004, 10.913885) (1.652902, 10.931981) (1.662911, 10.950048) (1.673029, 10.968087) (1.683256, 10.986098) (1.693591, 11.004081) (1.704032, 11.022035) (1.714579, 11.039961) (1.725231, 11.057859) (1.735986, 11.075728) (1.746845, 11.093568) (1.757805, 11.11138) (1.768866, 11.129164) (1.780026, 11.146919) (1.791285, 11.164645) (1.802642, 11.182343) (1.814097, 11.200012) (1.825648, 11.217652) (1.837296, 11.235263) (1.849038, 11.252845) (1.860875, 11.270399) (1.872805, 11.287923) (1.884828, 11.305418) (1.896944, 11.322883) (1.909151, 11.34032) (1.921449, 11.357727) (1.933839, 11.375104) (1.946318, 11.392452) (1.958886, 11.409771) (1.971543, 11.42706) (1.984288, 11.444318) (1.99712, 11.461547) (2.01004, 11.478746) (2.023046, 11.495914) (2.036138, 11.513053) (2.046681, 11.52674) (2.054627, 11.536991) (2.059941, 11.543819) (2.062603, 11.547232) knots 0 0 0 0 0 0 0.01428571 0.02857143 0.04285714 0.05714286 0.07142857 0.08571429 0.1 0.11428571 0.12857143 0.14285714 0.15714286 0.17142857 0.18571429 0.2 0.21428571 0.22857143 0.24285714 0.25714286 0.27142857 0.28571429 0.3 0.31428571 0.32857143 0.34285714 0.35714286 0.37142857 0.38571429 0.4 0.41428571 0.42857143 0.44285714 0.45714286 0.47142857 0.48571429 0.5 0.51428571 0.52857143 0.54285714 0.55714286 0.57142857 0.58571429 0.6 0.61428571 0.62857143 0.64285714 0.65714286 0.67142857 0.68571429 0.7 0.71428571 0.72857143 0.74285714 0.75714286 0.77142857 0.78571429 0.8 0.81428571 0.82857143 0.84285714 0.85714286 0.87142857 0.88571429 0.9 0.91428571 0.92857143 0.94285714 0.95714286 0.97142857 0.98571429 1 1 1 1 1 1
  line L11 (1.392385, 10.280342) -> (1.374596, 10.149004)
  arc A12 (1.374596, 10.149004) -> (0.631789, 10.222164) centre (0, 0) ccw
  line L12 (0.631789, 10.222164) -> (0.639965, 10.354449)
  spline S12 degree 5 poles (0.639965, 10.354449) (0.640208, 10.358374) (0.640603, 10.366227) (0.640924, 10.378011) (0.640838, 10.393732) (0.640021, 10.413398) (0.63869, 10.433079) (0.637035, 10.452771) (0.635204, 10.472474) (0.633256, 10.492186) (0.631191, 10.511906) (0.628972, 10.531631) (0.626547, 10.55136) (0.62388, 10.571092) (0.620964, 10.590826) (0.617818, 10.610561) (0.614469, 10.630298) (0.610951, 10.650036) (0.607289, 10.669774) (0.603492, 10.689512) (0.59956, 10.709251) (0.595488, 10.728988) (0.591267, 10.748725) (0.586892, 10.768459) (0.582365, 10.788192) (0.577689, 10.807922) (0.572872, 10.827649) (0.567922, 10.847374) (0.562843, 10.867095) (0.557639, 10.886813) (0.552312, 10.906526) (0.546861, 10.926236) (0.541285, 10.945941) (0.535586, 10.965642) (0.529764, 10.985337) (0.523821, 11.005027) (0.517759, 11.024712) (0.511582, 11.044391) (0.50529, 11.064064) (0.498885, 11.08373) (0.492368, 11.10339) (0.485741, 11.123044) (0.479003, 11.14269) (0.472156, 11.162329) (0.465201, 11.181961) (0.458138, 11.201585) (0.450968, 11.221201) (0.443694, 11.240809) (0.436315, 11.260409) (0.428833, 11.28) (0.421248, 11.299582) (0.413562, 11.319155) (0.405774, 11.33872) (0.397886, 11.358274) (0.389899, 11.377819) (0.381812, 11.397354) (0.373627, 11.41688) (0.365345, 11.436394) (0.356966, 11.455899) (0.34849, 11.475393) (0.339919, 11.494875) (0.331253, 11.514347) (0.322492, 11.533808) (0.313638, 11.553257) (0.304689, 11.572695) (0.295649, 11.592121) (0.286515, 11.611534) (0.277291, 11.630936) (0.267975, 11.650324) (0.258568, 11.6697) (0.249071, 11.689064) (0.241401, 11.704544) (0.235607, 11.716149) (0.231727, 11.723883) (0.229783, 11.727749) knots 0 0 0 0 0 0 0.01428571 0.02857143 0.04285714 0.05714286 0.07142857 0.08571429 0.1 0.11428571 0.12857143 0.14285714 0.15714286 0.17142857 0.18571429 0.2 0.21428571 0.22857143 0.24285714 0.25714286 0.27142857 0.28571429 0.3 0.31428571 0.32857143 0.34285714 0.35714286 0.37142857 0.38571429 0.4 0.41428571 0.42857143 0.44285714 0.45714286 0.47142857 0.48571429 0.5 0.51428571 0.52857143 0.54285714 0.55714286 0.57142857 0.58571429 0.6 0.61428571 0.62857143 0.64285714 0.65714286 0.67142857 0.68571429 0.7 0.71428571 0.72857143 0.74285714 0.75714286 0.77142857 0.78571429 0.8 0.81428571 0.82857143 0.84285714 0.85714286 0.87142857 0.88571429 0.9 0.91428571 0.92857143 0.94285714 0.95714286 0.97142857 0.98571429 1 1 1 1 1 1
  arc A13 (0.229783, 11.727749) -> (-0.229783, 11.727749) centre (0, 0) ccw
  spline S13 degree 5 poles (-0.639965, 10.354449) (-0.640208, 10.358374) (-0.640603, 10.366227) (-0.640924, 10.378011) (-0.640838, 10.393732) (-0.640021, 10.413398) (-0.63869, 10.433079) (-0.637035, 10.452771) (-0.635204, 10.472474) (-0.633256, 10.492186) (-0.631191, 10.511906) (-0.628972, 10.531631) (-0.626547, 10.55136) (-0.62388, 10.571092) (-0.620964, 10.590826) (-0.617818, 10.610561) (-0.614469, 10.630298) (-0.610951, 10.650036) (-0.607289, 10.669774) (-0.603492, 10.689512) (-0.59956, 10.709251) (-0.595488, 10.728988) (-0.591267, 10.748725) (-0.586892, 10.768459) (-0.582365, 10.788192) (-0.577689, 10.807922) (-0.572872, 10.827649) (-0.567922, 10.847374) (-0.562843, 10.867095) (-0.557639, 10.886813) (-0.552312, 10.906526) (-0.546861, 10.926236) (-0.541285, 10.945941) (-0.535586, 10.965642) (-0.529764, 10.985337) (-0.523821, 11.005027) (-0.517759, 11.024712) (-0.511582, 11.044391) (-0.50529, 11.064064) (-0.498885, 11.08373) (-0.492368, 11.10339) (-0.485741, 11.123044) (-0.479003, 11.14269) (-0.472156, 11.162329) (-0.465201, 11.181961) (-0.458138, 11.201585) (-0.450968, 11.221201) (-0.443694, 11.240809) (-0.436315, 11.260409) (-0.428833, 11.28) (-0.421248, 11.299582) (-0.413562, 11.319155) (-0.405774, 11.33872) (-0.397886, 11.358274) (-0.389899, 11.377819) (-0.381812, 11.397354) (-0.373627, 11.41688) (-0.365345, 11.436394) (-0.356966, 11.455899) (-0.34849, 11.475393) (-0.339919, 11.494875) (-0.331253, 11.514347) (-0.322492, 11.533808) (-0.313638, 11.553257) (-0.304689, 11.572695) (-0.295649, 11.592121) (-0.286515, 11.611534) (-0.277291, 11.630936) (-0.267975, 11.650324) (-0.258568, 11.6697) (-0.249071, 11.689064) (-0.241401, 11.704544) (-0.235607, 11.716149) (-0.231727, 11.723883) (-0.229783, 11.727749) knots 0 0 0 0 0 0 0.01428571 0.02857143 0.04285714 0.05714286 0.07142857 0.08571429 0.1 0.11428571 0.12857143 0.14285714 0.15714286 0.17142857 0.18571429 0.2 0.21428571 0.22857143 0.24285714 0.25714286 0.27142857 0.28571429 0.3 0.31428571 0.32857143 0.34285714 0.35714286 0.37142857 0.38571429 0.4 0.41428571 0.42857143 0.44285714 0.45714286 0.47142857 0.48571429 0.5 0.51428571 0.52857143 0.54285714 0.55714286 0.57142857 0.58571429 0.6 0.61428571 0.62857143 0.64285714 0.65714286 0.67142857 0.68571429 0.7 0.71428571 0.72857143 0.74285714 0.75714286 0.77142857 0.78571429 0.8 0.81428571 0.82857143 0.84285714 0.85714286 0.87142857 0.88571429 0.9 0.91428571 0.92857143 0.94285714 0.95714286 0.97142857 0.98571429 1 1 1 1 1 1
  line L13 (-0.639965, 10.354449) -> (-0.631789, 10.222164)
  arc A14 (-0.631789, 10.222164) -> (-1.374596, 10.149004) centre (0, 0) ccw
  line L14 (-1.374596, 10.149004) -> (-1.392385, 10.280342)